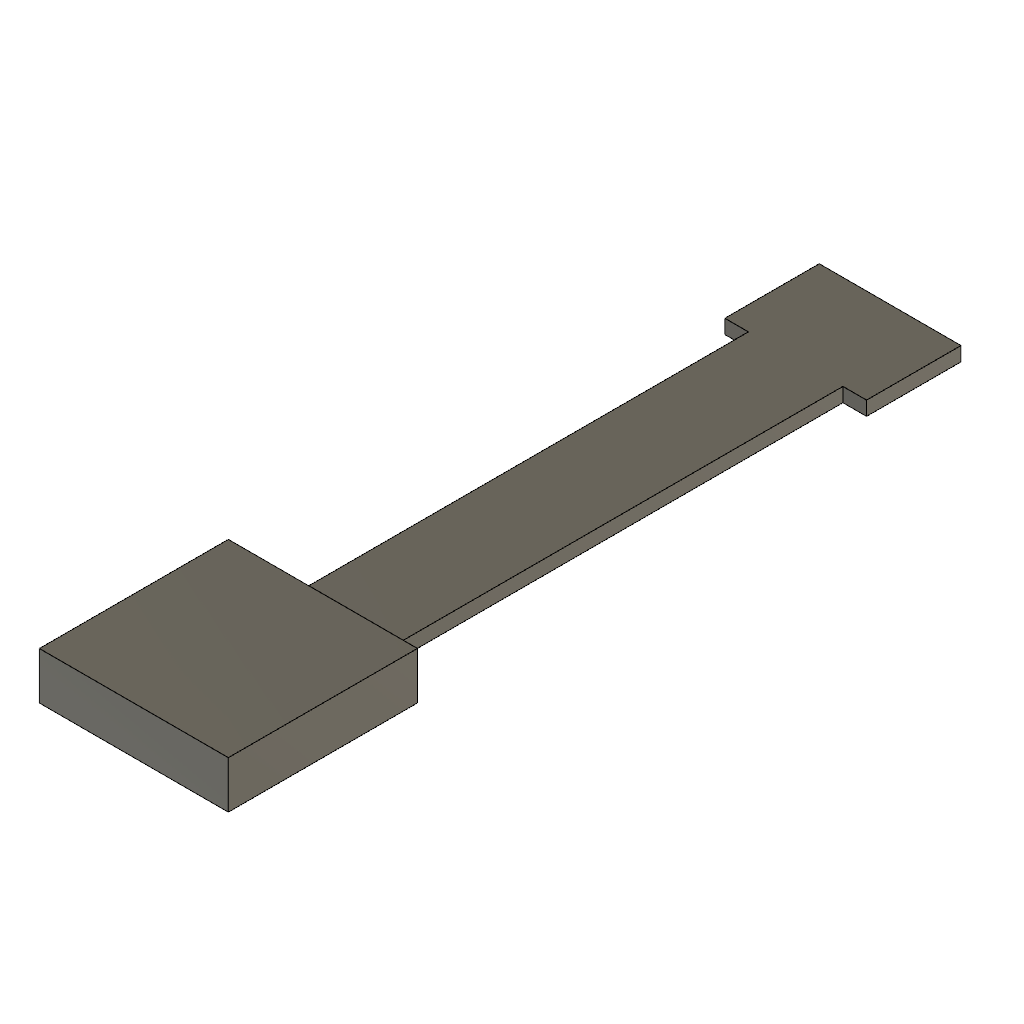
paindliktükk1 (Autodesk Fusion 360 design; units mm, degrees)
part number: 2026-09-12-17-24-39-228
Autodesk Fusion 360 part; units mm, degrees
sketch "Sketch1" plane through (0, 0, 0) normal (0, 0, 1) x (1, 0, 0)
  line L0 (-10, 0) -> (10, 0)
  line L1 (10, 0) -> (10, 20)
  line L2 (10, 20) -> (-10, 20)
  line L3 (-10, 20) -> (-10, 0)
extrude "Extrude1" add sketch "Sketch1" along normal blind 5 makes body 1
sketch "Sketch2" plane through (0, 0, 0) normal (0, 0, 1) x (1, 0, 0)
  line L0 (-5, 20) -> (5, 20)
  line L1 (5, 20) -> (5, 70)
  line L2 (5, 70) -> (-5, 70)
  line L3 (-5, 70) -> (-5, 20)
extrude "Extrude2" add sketch "Sketch2" along normal blind 1.5 separate body makes body 2
sketch "Sketch3" plane through (0, 0, 0) normal (0, 0, 1) x (1, 0, 0)
  line L0 (-7.5, 70) -> (7.5, 70)
  line L1 (7.5, 70) -> (7.5, 80)
  line L2 (7.5, 80) -> (-7.5, 80)
  line L3 (-7.5, 80) -> (-7.5, 70)
extrude "Extrude3" add sketch "Sketch3" along normal blind 1.5 separate body makes body 3
combine "Combine1" operation add target body 1 tool bodies 2
combine "Combine2" operation add target body 1 tool bodies 3
fillet "Fillet1" radius 3 3 edges at (5, 20, 0.75) (-5, 20, 0.75) (0, 20, 1.5) on bodies 1
equation "spring_thickness = 1.5 mm" comment "Flexible strip thickness"
equation "d4 = spring_thickness"
equation "d6 = spring_thickness"
